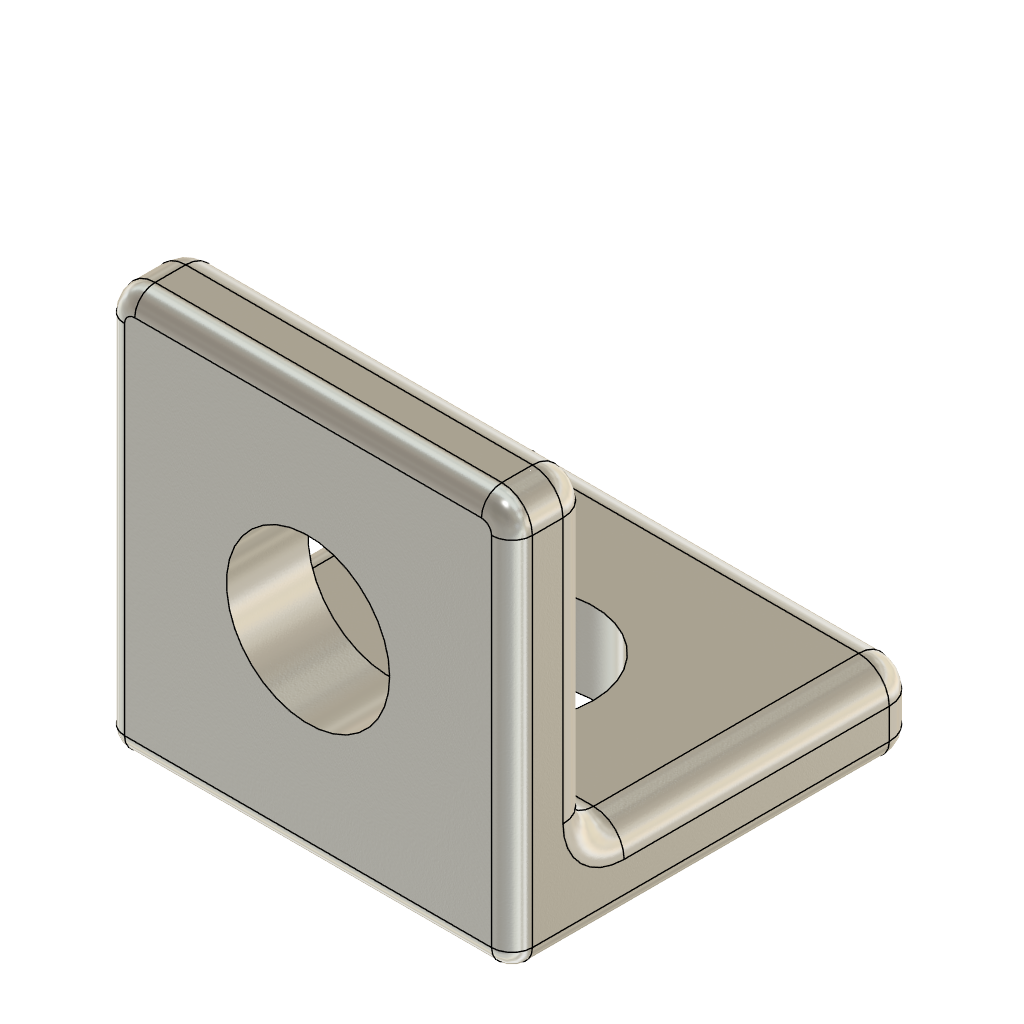
06-12 Angle bracket Placeholder (Autodesk Fusion 360 design; units mm, degrees)
Autodesk Fusion 360 part; units mm, degrees
sketch "Sketch1" plane through (0, 0, 0) normal (1, 0, 0) x (0, 1, 0)
  line L0 (0, 0) -> (40, 0)
  line L1 (40, 0) -> (40, 8)
  line L2 (40, 8) -> (8, 8)
  line L3 (8, 8) -> (8, 40)
  line L4 (8, 40) -> (0, 40)
  line L5 (0, 40) -> (0, 0)
  dimension "d1" = 8
  dimension "d2" = 8
  dimension "d3" = 32
  dimension "d4" = 32
  constraint coincident L0.start L5.end
  constraint horizontal L0
  constraint perpendicular L0 L1
  constraint perpendicular L1 L2
  constraint perpendicular L2 L3
  constraint perpendicular L3 L4
  constraint perpendicular L0 L5
  measures "d1" distance of L0.end L1.end
  measures "d2" distance of L3.end L4.end
  measures "d3" distance of L2.end L3.end
  measures "d4" distance of L1.end L2.end
extrude "Extrude1" add sketch "Sketch1" along normal blind 40
sketch "Sketch2" plane through (0, 8, 0) normal (0, 1, 0) x (-1, 0, 0)
  line L0 (0, 8) -> (0, 40)
  line L1 (0, 40) -> (-40, 40)
  line L2 (-40, 40) -> (-40, 8)
  line L3 (-40, 8) -> (0, 8)
  circle A0 centre (-20, 20) radius 8
  dimension "d7" = 16
  dimension "d8" = 12
  dimension "d9" = 20
  measures "d7" diameter of A0
  measures "d8" distance of L3 A0.centre
  measures "d9" distance of L0 A0.centre
extrude "Extrude2" cut sketch "Sketch2" against normal blind 30 contours A0
sketch "Sketch3" plane through (0, 0, 8) normal (0, 0, 1) x (-1, 0, 0)
  line L0 (0, -40) -> (0, -8)
  line L1 (0, -8) -> (-40, -8)
  line L2 (-40, -8) -> (-40, -40)
  line L3 (-40, -40) -> (0, -40)
  circle A0 centre (-20, -20) radius 8
  dimension "d12" = 16
  dimension "d13" = 12
  dimension "d14" = 20
  measures "d12" diameter of A0
  measures "d13" distance of L1 A0.centre
  measures "d14" distance of L2 A0.centre
extrude "Extrude3" cut sketch "Sketch3" against normal blind 30 contours A0
fillet "Fillet1" radius 3 10 edges at (0, 24, 8) (20, 40, 8) (40, 24, 8) (40, 8, 24) (40, 4, 40) (20, 8, 40) (40, 40, 4) (0, 40, 4) (0, 8, 24) (0, 4, 40)
fillet "Fillet1" radius 3 1 edges at (20, 8, 8)
fillet "Fillet1" radius 2 7 edges at (0, 20, 0) (20, 40, 0) (40, 20, 0) (20, 0, 0) (0, 0, 20) (40, 0, 20) (20, 0, 40)
